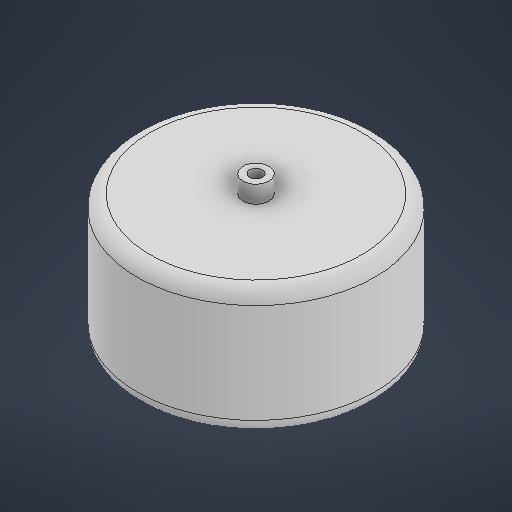
# Autodesk Inventor part: Roues_Grandes_Proto_D2S2
Saved by Autodesk Inventor 2026 (Build 300175000, 175)
## iProperties
Created: 2025-05-12
Part Number: Roues_Grandes_Proto_D2S2
Material: Générique
Document SubType Name: Modeling
Designer: Diogo
Density: 1 g/cm^3
Appearance: Par défaut
Author: Diogo
Autodesk Inventor part; units mm, degrees
ref_plane "YZ Plane" through (0, 0, 0) normal (1, 0, 0) x (0, 1, 0)
ref_plane "XZ Plane" through (0, 0, 0) normal (0, 1, 0) x (-1, 0, 0)
ref_plane "XY Plane" through (0, 0, 0) normal (0, 0, 1) x (1, 0, 0)
sketch "Esquisse1" plane through (0, 0, 0) normal (0, 0, 1) x (1, 0, 0)
  line L0 (0, 0) -> (0, 66)
  line L1 (0, 66) -> (6, 66)
  line L2 (6, 66) -> (6, 58)
  line L3 (6, 58) -> (55, 58)
  line L4 (55, 58) -> (55, 0)
  line L5 (55, 0) -> (0, 0)
  line L6 (0, -13.2) -> (0, 79.2) projected
  dimension "d0" = 55
  dimension "d1" = 58
  dimension "d2" = 66
  dimension "d3" = 6
  constraints: 12 end point, 4 perpendicular, 1 horizontal, 1 vertical
  measures "d0" distance of L4.end L0.start
  measures "d1" distance of L3.end L4.end
  measures "d2" distance of L0.start L0.end
  measures "d3" distance of L0.end L1.end
revolve "Révolution1" add sketch "Esquisse1" angle 360 about axis through (0, -10, 0) along (0, 1, 0)
sketch "Esquisse2" plane through (0, 66, 0) normal (0, 1, 0) x (1, 0, 0)
  circle A0 centre (0, 0) radius 6 projected
  constraints: 1 coincident
hole "Perçage1" at (0, 66, 0) direction (0, -1, 0) diameter 6 depth 14 tip angle 118
fillet "Congé1" radius 6 2 edges at (-55, 0, 0) (-55, 58, 0)
